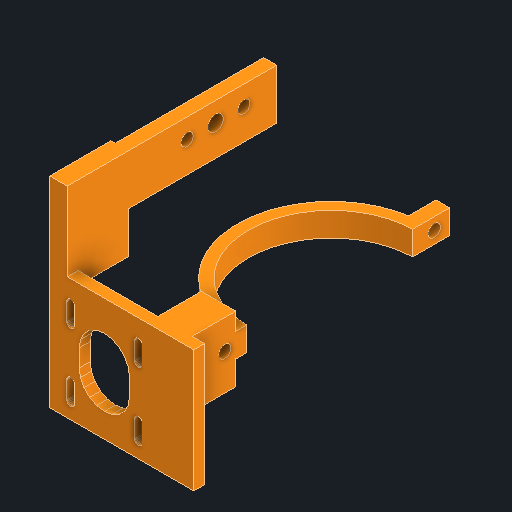
# Autodesk Inventor part: dec_motor_bracket
Saved by Autodesk Inventor 2027.1 (Build 311270010, 270A)
## iProperties
Created: 2026-11-04
Part Number: dec_motor_bracket
Material: Generic
Description: Dec motor bracket: tab on the Dec worm carrier (its 2x M5 lengthened to M5x25) + half clamp ring on the Dec housing + motor plate; print PETG/ASA
Document SubType Name: Modeling
Designer: Claude (from photos)
Density: 1 g/cm^3
Appearance: Orange
Author: alexg
Autodesk Inventor part; units mm, degrees
ref_plane "Work Plane1" through (0, 47, 0) normal (0, 1, 0) x (-1, 0, 0)
sketch "Clamp ring sketch" plane through (0, 47, 0) normal (0, 1, 0) x (-1, 0, 0)
  circle A0 centre (-187, 0) radius 43
  circle A1 centre (-187, 0) radius 38
  constraints: 2 centre point
extrude "Clamp ring" add sketch "Clamp ring sketch" along normal blind 11
ref_plane "Work Plane2" through (0, 47, 0) normal (0, 1, 0) x (-1, 0, 0)
sketch "Keep the worm-side half sketch" plane through (0, 47, 0) normal (0, 1, 0) x (-1, 0, 0)
  line L0 (-186.25, -60) -> (-247, -60)
  line L1 (-247, -60) -> (-247, 60)
  line L2 (-247, 60) -> (-186.25, 60)
  line L3 (-186.25, 60) -> (-186.25, -60)
  constraints: 8 end point, 2 parallel, 1 horizontal, 1 perpendicular
extrude "Keep the worm-side half" cut sketch "Keep the worm-side half sketch" along normal blind 11
ref_plane "Work Plane3" through (0, 47, 0) normal (0, 1, 0) x (-1, 0, 0)
sketch "Clamp ears sketch" plane through (0, 47, 0) normal (0, 1, 0) x (-1, 0, 0)
  line L0 (-180, 41) -> (-186.25, 41)
  line L1 (-186.25, 41) -> (-186.25, 55)
  line L2 (-186.25, 55) -> (-180, 55)
  line L3 (-180, 55) -> (-180, 41)
  line L4 (-180, -55) -> (-186.25, -55)
  line L5 (-186.25, -55) -> (-186.25, -41)
  line L6 (-186.25, -41) -> (-180, -41)
  line L7 (-180, -41) -> (-180, -55)
  constraints: 16 end point, 4 parallel, 2 horizontal, 2 perpendicular
extrude "Clamp ears" add sketch "Clamp ears sketch" along normal blind 11
ref_plane "Work Plane4" through (0, 47, 0) normal (0, 1, 0) x (-1, 0, 0)
sketch "Web core sketch" plane through (0, 47, 0) normal (0, 1, 0) x (-1, 0, 0)
  line L0 (-170.5, 31) -> (-186.25, 31)
  line L1 (-186.25, 31) -> (-186.25, 63)
  line L2 (-186.25, 63) -> (-170.5, 63)
  line L3 (-170.5, 63) -> (-170.5, 31)
  constraints: 8 end point, 2 parallel, 1 horizontal, 1 perpendicular
extrude "Web core" add sketch "Web core sketch" along normal blind 11
ref_plane "Work Plane5" through (0, 36, 0) normal (0, 1, 0) x (-1, 0, 0)
sketch "Web gusset sketch" plane through (0, 36, 0) normal (0, 1, 0) x (-1, 0, 0)
  line L0 (-170.5, 43) -> (-186.25, 43)
  line L1 (-186.25, 43) -> (-186.25, 63.5)
  line L2 (-186.25, 63.5) -> (-170.5, 63.5)
  line L3 (-170.5, 63.5) -> (-170.5, 43)
  constraints: 8 end point, 2 parallel, 1 horizontal, 1 perpendicular
extrude "Web gusset" add sketch "Web gusset sketch" along normal blind 30
ref_plane "Work Plane6" through (0, 36, 0) normal (0, 1, 0) x (-1, 0, 0)
sketch "Housing bore sketch" plane through (0, 36, 0) normal (0, 1, 0) x (-1, 0, 0)
  circle A0 centre (-187, 0) radius 38
  constraints: 1 centre point
extrude "Housing bore" cut sketch "Housing bore sketch" along normal blind 30
ref_plane "Work Plane7" through (0, 0, 63) normal (0, 0, 1) x (1, 0, 0)
sketch "Motor plate (slots +-4 along the belt) sketch" plane through (0, 0, 63) normal (0, 0, 1) x (1, 0, 0)
  line L0 (126, 10) -> (192, 10)
  line L1 (192, 10) -> (192, 66)
  line L2 (192, 66) -> (126, 66)
  line L3 (126, 66) -> (126, 10)
  line L4 (139.5, 32.58) -> (140.0629, 29.0263)
  line L5 (140.0629, 29.0263) -> (141.6963, 25.8205)
  line L6 (141.6963, 25.8205) -> (144.2405, 23.2763)
  line L7 (144.2405, 23.2763) -> (147.4463, 21.6429)
  line L8 (147.4463, 21.6429) -> (151, 21.08)
  line L9 (151, 21.08) -> (154.5537, 21.6429)
  line L10 (154.5537, 21.6429) -> (157.7595, 23.2763)
  line L11 (157.7595, 23.2763) -> (160.3037, 25.8205)
  line L12 (160.3037, 25.8205) -> (161.9371, 29.0263)
  line L13 (161.9371, 29.0263) -> (162.5, 32.58)
  line L14 (162.5, 32.58) -> (162.5, 40.58)
  line L15 (162.5, 40.58) -> (161.9371, 44.1337)
  line L16 (161.9371, 44.1337) -> (160.3037, 47.3395)
  line L17 (160.3037, 47.3395) -> (157.7595, 49.8837)
  line L18 (157.7595, 49.8837) -> (154.5537, 51.5171)
  line L19 (154.5537, 51.5171) -> (151, 52.08)
  line L20 (151, 52.08) -> (147.4463, 51.5171)
  line L21 (147.4463, 51.5171) -> (144.2405, 49.8837)
  line L22 (144.2405, 49.8837) -> (141.6963, 47.3395)
  line L23 (141.6963, 47.3395) -> (140.0629, 44.1337)
  line L24 (140.0629, 44.1337) -> (139.5, 40.58)
  line L25 (139.5, 40.58) -> (139.5, 32.58)
  line L26 (133.8, 17.08) -> (133.8832, 16.5547)
  line L27 (133.8832, 16.5547) -> (134.1247, 16.0808)
  line L28 (134.1247, 16.0808) -> (134.5008, 15.7047)
  line L29 (134.5008, 15.7047) -> (134.9747, 15.4632)
  line L30 (134.9747, 15.4632) -> (135.5, 15.38)
  line L31 (135.5, 15.38) -> (136.0253, 15.4632)
  line L32 (136.0253, 15.4632) -> (136.4992, 15.7047)
  line L33 (136.4992, 15.7047) -> (136.8753, 16.0808)
  line L34 (136.8753, 16.0808) -> (137.1168, 16.5547)
  line L35 (137.1168, 16.5547) -> (137.2, 17.08)
  line L36 (137.2, 17.08) -> (137.2, 25.08)
  line L37 (137.2, 25.08) -> (137.1168, 25.6053)
  line L38 (137.1168, 25.6053) -> (136.8753, 26.0792)
  line L39 (136.8753, 26.0792) -> (136.4992, 26.4553)
  line L40 (136.4992, 26.4553) -> (136.0253, 26.6968)
  line L41 (136.0253, 26.6968) -> (135.5, 26.78)
  line L42 (135.5, 26.78) -> (134.9747, 26.6968)
  line L43 (134.9747, 26.6968) -> (134.5008, 26.4553)
  line L44 (134.5008, 26.4553) -> (134.1247, 26.0792)
  line L45 (134.1247, 26.0792) -> (133.8832, 25.6053)
  line L46 (133.8832, 25.6053) -> (133.8, 25.08)
  line L47 (133.8, 25.08) -> (133.8, 17.08)
  line L48 (133.8, 48.08) -> (133.8832, 47.5547)
  line L49 (133.8832, 47.5547) -> (134.1247, 47.0808)
  line L50 (134.1247, 47.0808) -> (134.5008, 46.7047)
  line L51 (134.5008, 46.7047) -> (134.9747, 46.4632)
  line L52 (134.9747, 46.4632) -> (135.5, 46.38)
  line L53 (135.5, 46.38) -> (136.0253, 46.4632)
  line L54 (136.0253, 46.4632) -> (136.4992, 46.7047)
  line L55 (136.4992, 46.7047) -> (136.8753, 47.0808)
  line L56 (136.8753, 47.0808) -> (137.1168, 47.5547)
  line L57 (137.1168, 47.5547) -> (137.2, 48.08)
  line L58 (137.2, 48.08) -> (137.2, 56.08)
  line L59 (137.2, 56.08) -> (137.1168, 56.6053)
  line L60 (137.1168, 56.6053) -> (136.8753, 57.0792)
  line L61 (136.8753, 57.0792) -> (136.4992, 57.4553)
  line L62 (136.4992, 57.4553) -> (136.0253, 57.6968)
  line L63 (136.0253, 57.6968) -> (135.5, 57.78)
  line L64 (135.5, 57.78) -> (134.9747, 57.6968)
  line L65 (134.9747, 57.6968) -> (134.5008, 57.4553)
  line L66 (134.5008, 57.4553) -> (134.1247, 57.0792)
  line L67 (134.1247, 57.0792) -> (133.8832, 56.6053)
  line L68 (133.8832, 56.6053) -> (133.8, 56.08)
  line L69 (133.8, 56.08) -> (133.8, 48.08)
  line L70 (164.8, 17.08) -> (164.8832, 16.5547)
  line L71 (164.8832, 16.5547) -> (165.1247, 16.0808)
  line L72 (165.1247, 16.0808) -> (165.5008, 15.7047)
  line L73 (165.5008, 15.7047) -> (165.9747, 15.4632)
  line L74 (165.9747, 15.4632) -> (166.5, 15.38)
  line L75 (166.5, 15.38) -> (167.0253, 15.4632)
  line L76 (167.0253, 15.4632) -> (167.4992, 15.7047)
  line L77 (167.4992, 15.7047) -> (167.8753, 16.0808)
  line L78 (167.8753, 16.0808) -> (168.1168, 16.5547)
  line L79 (168.1168, 16.5547) -> (168.2, 17.08)
  line L80 (168.2, 17.08) -> (168.2, 25.08)
  line L81 (168.2, 25.08) -> (168.1168, 25.6053)
  line L82 (168.1168, 25.6053) -> (167.8753, 26.0792)
  line L83 (167.8753, 26.0792) -> (167.4992, 26.4553)
  line L84 (167.4992, 26.4553) -> (167.0253, 26.6968)
  line L85 (167.0253, 26.6968) -> (166.5, 26.78)
  line L86 (166.5, 26.78) -> (165.9747, 26.6968)
  line L87 (165.9747, 26.6968) -> (165.5008, 26.4553)
  line L88 (165.5008, 26.4553) -> (165.1247, 26.0792)
  line L89 (165.1247, 26.0792) -> (164.8832, 25.6053)
  line L90 (164.8832, 25.6053) -> (164.8, 25.08)
  line L91 (164.8, 25.08) -> (164.8, 17.08)
  line L92 (164.8, 48.08) -> (164.8832, 47.5547)
  line L93 (164.8832, 47.5547) -> (165.1247, 47.0808)
  line L94 (165.1247, 47.0808) -> (165.5008, 46.7047)
  line L95 (165.5008, 46.7047) -> (165.9747, 46.4632)
  line L96 (165.9747, 46.4632) -> (166.5, 46.38)
  line L97 (166.5, 46.38) -> (167.0253, 46.4632)
  line L98 (167.0253, 46.4632) -> (167.4992, 46.7047)
  line L99 (167.4992, 46.7047) -> (167.8753, 47.0808)
  line L100 (167.8753, 47.0808) -> (168.1168, 47.5547)
  line L101 (168.1168, 47.5547) -> (168.2, 48.08)
  line L102 (168.2, 48.08) -> (168.2, 56.08)
  line L103 (168.2, 56.08) -> (168.1168, 56.6053)
  line L104 (168.1168, 56.6053) -> (167.8753, 57.0792)
  line L105 (167.8753, 57.0792) -> (167.4992, 57.4553)
  line L106 (167.4992, 57.4553) -> (167.0253, 57.6968)
  line L107 (167.0253, 57.6968) -> (166.5, 57.78)
  line L108 (166.5, 57.78) -> (165.9747, 57.6968)
  line L109 (165.9747, 57.6968) -> (165.5008, 57.4553)
  line L110 (165.5008, 57.4553) -> (165.1247, 57.0792)
  line L111 (165.1247, 57.0792) -> (164.8832, 56.6053)
  line L112 (164.8832, 56.6053) -> (164.8, 56.08)
  line L113 (164.8, 56.08) -> (164.8, 48.08)
  constraints: 228 end point, 2 parallel, 1 horizontal, 1 perpendicular
extrude "Motor plate (slots +-4 along the belt)" add sketch "Motor plate (slots +-4 along the belt) sketch" along normal blind 5
ref_plane "Work Plane8" through (128, 0, 0) normal (1, 0, 0) x (0, 1, 0)
sketch "Tab on Dec worm carrier sketch" plane through (128, 0, 0) normal (1, 0, 0) x (0, 1, 0)
  line L0 (79, -28) -> (102, -28)
  line L1 (102, -28) -> (102, 44)
  line L2 (102, 44) -> (79, 44)
  line L3 (79, 44) -> (79, -28)
  constraints: 8 end point, 2 parallel, 1 horizontal, 1 perpendicular
extrude "Tab on Dec worm carrier" add sketch "Tab on Dec worm carrier sketch" along normal blind 6
ref_plane "Work Plane9" through (126, 0, 0) normal (1, 0, 0) x (0, 1, 0)
sketch "Arm from tab to plate sketch" plane through (126, 0, 0) normal (1, 0, 0) x (0, 1, 0)
  line L0 (60, 40) -> (102, 40)
  line L1 (102, 40) -> (102, 68)
  line L2 (102, 68) -> (60, 68)
  line L3 (60, 68) -> (60, 40)
  constraints: 8 end point, 2 parallel, 1 horizontal, 1 perpendicular
extrude "Arm from tab to plate" add sketch "Arm from tab to plate sketch" along normal blind 8
ref_plane "Work Plane10" through (128, 0, 0) normal (1, 0, 0) x (0, 1, 0)
sketch "Carrier M5 holes + grub access sketch" plane through (128, 0, 0) normal (1, 0, 0) x (0, 1, 0)
  circle A0 centre (93, 13) radius 2.75
  circle A1 centre (93, -13) radius 2.75
  circle A2 centre (93, 0) radius 3.5
  constraints: 3 centre point
extrude "Carrier M5 holes + grub access" cut sketch "Carrier M5 holes + grub access sketch" along normal blind 6
ref_plane "Work Plane11" through (186.25, 0, 0) normal (1, 0, 0) x (0, 1, 0)
sketch "M4 heat-set insert pockets sketch" plane through (186.25, 0, 0) normal (1, 0, 0) x (0, 1, 0)
  circle A0 centre (52.5, 48) radius 2.8
  circle A1 centre (52.5, -48) radius 2.8
  constraints: 2 centre point
extrude "M4 heat-set insert pockets" cut sketch "M4 heat-set insert pockets sketch" against normal blind 10
body "Solid1"
